Autodesk Fusion 360 part; units mm, degrees
(part 5 of 8)
  spline S109 degree 5 poles (-4.725934, 4.389539) (-4.725181, 4.387551) (-4.723672, 4.383579) (-4.721399, 4.377629) (-4.718349, 4.369712) (-4.714504, 4.359843) (-4.710627, 4.350002) (-4.706718, 4.340188) (-4.702776, 4.330401) (-4.698802, 4.320643) (-4.694795, 4.310913) (-4.690755, 4.301211) (-4.686683, 4.291538) (-4.682577, 4.281894) (-4.678439, 4.272279) (-4.674267, 4.262693) (-4.670062, 4.253137) (-4.665824, 4.243611) (-4.661551, 4.234115) (-4.657246, 4.22465) (-4.652906, 4.215215) (-4.648532, 4.205811) (-4.644124, 4.196439) (-4.639682, 4.187098) (-4.635205, 4.177788) (-4.630693, 4.168512) (-4.626147, 4.159267) (-4.621565, 4.150055) (-4.616948, 4.140877) (-4.612296, 4.131732) (-4.607608, 4.122621) (-4.602883, 4.113544) (-4.598123, 4.104502) (-4.593326, 4.095495) (-4.588492, 4.086524) (-4.583621, 4.077589) (-4.578713, 4.068689) (-4.573767, 4.059827) (-4.568784, 4.051001) (-4.563762, 4.042214) (-4.558702, 4.033464) (-4.553602, 4.024755) (-4.548462, 4.016085) (-4.543281, 4.007456) (-4.538061, 3.998867) (-4.532799, 3.99032) (-4.527498, 3.981813) (-4.522155, 3.973349) (-4.516771, 3.964927) (-4.511343, 3.95655) (-4.505871, 3.948219) (-4.500351, 3.939937) (-4.494784, 3.931705) (-4.489169, 3.923523) (-4.483506, 3.915391) (-4.477798, 3.907307) (-4.472045, 3.89927) (-4.466248, 3.891282) (-4.460403, 3.883345) (-4.454505, 3.875465) (-4.448545, 3.867651) (-4.442516, 3.859911) (-4.437505, 3.853618) (-4.433679, 3.848895) (-4.43107, 3.845708) (-4.429696, 3.844038) (-4.429564, 3.843877) knots -1 -1 -1 -1 -1 -1 -0.98571429 -0.97142857 -0.95714286 -0.94285714 -0.92857143 -0.91428571 -0.9 -0.88571429 -0.87142857 -0.85714286 -0.84285714 -0.82857143 -0.81428571 -0.8 -0.78571429 -0.77142857 -0.75714286 -0.74285714 -0.72857143 -0.71428571 -0.7 -0.68571429 -0.67142857 -0.65714286 -0.64285714 -0.62857143 -0.61428571 -0.6 -0.58571429 -0.57142857 -0.55714286 -0.54285714 -0.52857143 -0.51428571 -0.5 -0.48571429 -0.47142857 -0.45714286 -0.44285714 -0.42857143 -0.41428571 -0.4 -0.38571429 -0.37142857 -0.35714286 -0.34285714 -0.32857143 -0.31428571 -0.3 -0.28571429 -0.27142857 -0.25714286 -0.24285714 -0.22857143 -0.21428571 -0.2 -0.18571429 -0.17142857 -0.15714286 -0.14285714 -0.12857143 -0.1270499 -0.1270499 -0.1270499 -0.1270499 -0.1270499 -0.1270499
  spline S110 degree 3 poles (-4.616916, 3.6167) (-4.599749, 3.607383) (-4.580926, 3.601508) (-4.542089, 3.597304) (-4.522445, 3.599015) (-4.484919, 3.60987) (-4.467396, 3.618911) (-4.436801, 3.6432) (-4.424022, 3.658217) (-4.404939, 3.692303) (-4.398817, 3.711047) (-4.394104, 3.749826) (-4.395557, 3.76949) (-4.403528, 3.798464) (-4.407377, 3.808284) (-4.417066, 3.826956) (-4.422879, 3.835757) (-4.429564, 3.843877) knots 0 0 0 0 0.00585967 0.00585967 0.01171933 0.01171933 0.017579 0.017579 0.02343867 0.02343867 0.02929834 0.02929834 0.035158 0.035158 0.03831344 0.03831344 0.04146887 0.04146887 0.04146887 0.04146887
  spline S111 degree 5 poles (-4.616916, 3.6167) (-4.617099, 3.616799) (-4.619, 3.61783) (-4.622625, 3.619784) (-4.62799, 3.622641) (-4.635122, 3.626362) (-4.643869, 3.630807) (-4.652674, 3.63517) (-4.661533, 3.639461) (-4.670438, 3.643687) (-4.679384, 3.647858) (-4.688368, 3.651975) (-4.697391, 3.65604) (-4.706453, 3.66005) (-4.715554, 3.664005) (-4.724696, 3.667903) (-4.733877, 3.671745) (-4.743097, 3.675531) (-4.752355, 3.679265) (-4.761647, 3.682947) (-4.770974, 3.68658) (-4.780335, 3.690166) (-4.789728, 3.693703) (-4.799153, 3.697193) (-4.808611, 3.700636) (-4.818101, 3.704031) (-4.827622, 3.70738) (-4.837174, 3.710682) (-4.846757, 3.713939) (-4.85637, 3.717151) (-4.866012, 3.720318) (-4.875683, 3.723442) (-4.885383, 3.726523) (-4.89511, 3.72956) (-4.904866, 3.732555) (-4.914649, 3.735507) (-4.924459, 3.738416) (-4.934296, 3.741284) (-4.944159, 3.74411) (-4.954049, 3.746895) (-4.963964, 3.749639) (-4.973905, 3.752342) (-4.983871, 3.755005) (-4.993863, 3.757628) (-5.003879, 3.760211) (-5.013919, 3.762753) (-5.023984, 3.765257) (-5.034072, 3.767721) (-5.044184, 3.770146) (-5.05432, 3.772532) (-5.064479, 3.774879) (-5.07466, 3.777188) (-5.084865, 3.779458) (-5.095092, 3.781691) (-5.105341, 3.783885) (-5.115613, 3.786041) (-5.125906, 3.78816) (-5.136221, 3.790241) (-5.146558, 3.792285) (-5.156916, 3.794291) (-5.167294, 3.79626) (-5.177694, 3.798193) (-5.188114, 3.800088) (-5.196467, 3.801575) (-5.202741, 3.802674) (-5.206928, 3.803399) (-5.209022, 3.803759) knots 0.1270499 0.1270499 0.1270499 0.1270499 0.1270499 0.1270499 0.12857143 0.14285714 0.15714286 0.17142857 0.18571429 0.2 0.21428571 0.22857143 0.24285714 0.25714286 0.27142857 0.28571429 0.3 0.31428571 0.32857143 0.34285714 0.35714286 0.37142857 0.38571429 0.4 0.41428571 0.42857143 0.44285714 0.45714286 0.47142857 0.48571429 0.5 0.51428571 0.52857143 0.54285714 0.55714286 0.57142857 0.58571429 0.6 0.61428571 0.62857143 0.64285714 0.65714286 0.67142857 0.68571429 0.7 0.71428571 0.72857143 0.74285714 0.75714286 0.77142857 0.78571429 0.8 0.81428571 0.82857143 0.84285714 0.85714286 0.87142857 0.88571429 0.9 0.91428571 0.92857143 0.94285714 0.95714286 0.97142857 0.98571429 1 1 1 1 1 1
  arc A37 (-5.209022, 3.803759) -> (-5.340608, 3.616685) centre (0, 0) ccw
  spline S112 degree 5 poles (-5.340608, 3.616685) (-5.33956, 3.614836) (-5.337463, 3.61114) (-5.334308, 3.605607) (-5.330085, 3.598248) (-5.324779, 3.589082) (-5.319445, 3.579948) (-5.314084, 3.570845) (-5.308694, 3.561776) (-5.303277, 3.552738) (-5.297832, 3.543734) (-5.292359, 3.534762) (-5.286857, 3.525824) (-5.281328, 3.51692) (-5.27577, 3.508049) (-5.270184, 3.499213) (-5.264569, 3.490411) (-5.258926, 3.481643) (-5.253255, 3.472911) (-5.247554, 3.464213) (-5.241825, 3.455552) (-5.236067, 3.446926) (-5.23028, 3.438336) (-5.224464, 3.429783) (-5.218618, 3.421266) (-5.212744, 3.412786) (-5.206839, 3.404344) (-5.200905, 3.39594) (-5.194941, 3.387574) (-5.188947, 3.379246) (-5.182923, 3.370958) (-5.176869, 3.362708) (-5.170784, 3.354499) (-5.164668, 3.34633) (-5.158522, 3.338202) (-5.152344, 3.330115) (-5.146135, 3.322069) (-5.139894, 3.314065) (-5.133622, 3.306104) (-5.127318, 3.298185) (-5.120981, 3.290311) (-5.114611, 3.282482) (-5.108208, 3.274699) (-5.101771, 3.266961) (-5.095301, 3.25927) (-5.088796, 3.251626) (-5.082258, 3.244029) (-5.075686, 3.236479) (-5.069079, 3.228978) (-5.062437, 3.221527) (-5.055757, 3.21413) (-5.049038, 3.206787) (-5.042279, 3.199501) (-5.03548, 3.192273) (-5.028643, 3.1851) (-5.021768, 3.177982) (-5.014856, 3.170918) (-5.007907, 3.163908) (-5.000919, 3.156956) (-4.993887, 3.150069) (-4.986804, 3.143257) (-4.979664, 3.136528) (-4.973751, 3.131073) (-4.969249, 3.126989) (-4.966185, 3.124238) (-4.964572, 3.122797) (-4.964416, 3.122659) knots -1 -1 -1 -1 -1 -1 -0.98571429 -0.97142857 -0.95714286 -0.94285714 -0.92857143 -0.91428571 -0.9 -0.88571429 -0.87142857 -0.85714286 -0.84285714 -0.82857143 -0.81428571 -0.8 -0.78571429 -0.77142857 -0.75714286 -0.74285714 -0.72857143 -0.71428571 -0.7 -0.68571429 -0.67142857 -0.65714286 -0.64285714 -0.62857143 -0.61428571 -0.6 -0.58571429 -0.57142857 -0.55714286 -0.54285714 -0.52857143 -0.51428571 -0.5 -0.48571429 -0.47142857 -0.45714286 -0.44285714 -0.42857143 -0.41428571 -0.4 -0.38571429 -0.37142857 -0.35714286 -0.34285714 -0.32857143 -0.31428571 -0.3 -0.28571429 -0.27142857 -0.25714286 -0.24285714 -0.22857143 -0.21428571 -0.2 -0.18571429 -0.17142857 -0.15714286 -0.14285714 -0.12857143 -0.1270499 -0.1270499 -0.1270499 -0.1270499 -0.1270499 -0.1270499
  spline S113 degree 3 poles (-5.114894, 2.869545) (-5.096506, 2.862957) (-5.077007, 2.860025) (-5.037983, 2.861798) (-5.018831, 2.866488) (-4.983402, 2.882944) (-4.967464, 2.894554) (-4.940935, 2.923229) (-4.930598, 2.94002) (-4.916942, 2.97662) (-4.913754, 2.996079) (-4.915015, 3.035123) (-4.919453, 3.054335) (-4.931753, 3.081752) (-4.937056, 3.09087) (-4.949482, 3.107844) (-4.95657, 3.115654) (-4.964416, 3.122659) knots 0 0 0 0 0.00585967 0.00585967 0.01171933 0.01171933 0.017579 0.017579 0.02343867 0.02343867 0.02929834 0.02929834 0.035158 0.035158 0.03831344 0.03831344 0.04146887 0.04146887 0.04146887 0.04146887
  spline S114 degree 5 poles (-5.114894, 2.869545) (-5.11509, 2.869615) (-5.117126, 2.870344) (-5.121007, 2.871722) (-5.126746, 2.873726) (-5.134362, 2.876315) (-5.143685, 2.879372) (-5.153053, 2.88234) (-5.162463, 2.885228) (-5.171908, 2.888046) (-5.181386, 2.890802) (-5.190894, 2.893499) (-5.200432, 2.896139) (-5.209999, 2.898719) (-5.219598, 2.901239) (-5.229227, 2.903696) (-5.238887, 2.906091) (-5.248578, 2.908425) (-5.258296, 2.910702) (-5.268042, 2.912922) (-5.277814, 2.915089) (-5.287612, 2.917204) (-5.297435, 2.919266) (-5.307283, 2.921276) (-5.317155, 2.923235) (-5.327052, 2.925142) (-5.336973, 2.926998) (-5.346918, 2.928803) (-5.356886, 2.930559) (-5.366876, 2.932266) (-5.376889, 2.933924) (-5.386923, 2.935535) (-5.396979, 2.937099) (-5.407056, 2.938616) (-5.417155, 2.940086) (-5.427273, 2.94151) (-5.437413, 2.942889) (-5.447572, 2.944221) (-5.457751, 2.945508) (-5.46795, 2.946751) (-5.478168, 2.947949) (-5.488406, 2.949103) (-5.498661, 2.950214) (-5.508936, 2.95128) (-5.519229, 2.952304) (-5.52954, 2.953284) (-5.539868, 2.954222) (-5.550215, 2.955117) (-5.560579, 2.95597) (-5.57096, 2.956781) (-5.581358, 2.95755) (-5.591772, 2.958278) (-5.602204, 2.958964) (-5.612652, 2.959609) (-5.623116, 2.960213) (-5.633597, 2.960776) (-5.644093, 2.961298) (-5.654605, 2.96178) (-5.665132, 2.962222) (-5.675675, 2.962624) (-5.686232, 2.962986) (-5.696805, 2.963308) (-5.707393, 2.963591) (-5.715875, 2.963785) (-5.722243, 2.963913) (-5.726491, 2.963991) (-5.728616, 2.964027) knots 0.1270499 0.1270499 0.1270499 0.1270499 0.1270499 0.1270499 0.12857143 0.14285714 0.15714286 0.17142857 0.18571429 0.2 0.21428571 0.22857143 0.24285714 0.25714286 0.27142857 0.28571429 0.3 0.31428571 0.32857143 0.34285714 0.35714286 0.37142857 0.38571429 0.4 0.41428571 0.42857143 0.44285714 0.45714286 0.47142857 0.48571429 0.5 0.51428571 0.52857143 0.54285714 0.55714286 0.57142857 0.58571429 0.6 0.61428571 0.62857143 0.64285714 0.65714286 0.67142857 0.68571429 0.7 0.71428571 0.72857143 0.74285714 0.75714286 0.77142857 0.78571429 0.8 0.81428571 0.82857143 0.84285714 0.85714286 0.87142857 0.88571429 0.9 0.91428571 0.92857143 0.94285714 0.95714286 0.97142857 0.98571429 1 1 1 1 1 1
  arc A38 (-5.728616, 2.964027) -> (-5.830102, 2.759059) centre (0, 0) ccw
  spline S115 degree 5 poles (-5.830102, 2.759059) (-5.828785, 2.757391) (-5.826148, 2.754059) (-5.822186, 2.749072) (-5.816889, 2.742445) (-5.810246, 2.734196) (-5.80358, 2.725983) (-5.796892, 2.717805) (-5.790181, 2.709665) (-5.783448, 2.70156) (-5.776692, 2.693492) (-5.769913, 2.685462) (-5.763112, 2.677468) (-5.756288, 2.669512) (-5.749441, 2.661594) (-5.742572, 2.653714) (-5.735679, 2.645872) (-5.728764, 2.638069) (-5.721826, 2.630304) (-5.714865, 2.622579) (-5.707881, 2.614893) (-5.700873, 2.607247) (-5.693843, 2.599642) (-5.686789, 2.592076) (-5.679712, 2.584552) (-5.672612, 2.577068) (-5.665488, 2.569627) (-5.658341, 2.562227) (-5.651169, 2.554869) (-5.643975, 2.547554) (-5.636756, 2.540282) (-5.629513, 2.533053) (-5.622246, 2.525869) (-5.614955, 2.51873) (-5.60764, 2.511635) (-5.6003, 2.504585) (-5.592936, 2.497582) (-5.585547, 2.490624) (-5.578133, 2.483714) (-5.570694, 2.476851) (-5.563229, 2.470036) (-5.555739, 2.463271) (-5.548223, 2.456556) (-5.54068, 2.449892) (-5.533111, 2.443279) (-5.525516, 2.436717) (-5.517895, 2.430207) (-5.510248, 2.423749) (-5.502573, 2.417344) (-5.494871, 2.410995) (-5.48714, 2.404704) (-5.479379, 2.398473) (-5.471587, 2.392304) (-5.463765, 2.386198) (-5.455912, 2.380153) (-5.448031, 2.374168) (-5.440122, 2.368242) (-5.432185, 2.362375) (-5.424218, 2.356571) (-5.416216, 2.350839) (-5.408177, 2.345187) (-5.400093, 2.339627) (-5.393417, 2.335139) (-5.388344, 2.33179) (-5.384896, 2.329539) (-5.383082, 2.328361) (-5.382907, 2.328248) knots -1 -1 -1 -1 -1 -1 -0.98571429 -0.97142857 -0.95714286 -0.94285714 -0.92857143 -0.91428571 -0.9 -0.88571429 -0.87142857 -0.85714286 -0.84285714 -0.82857143 -0.81428571 -0.8 -0.78571429 -0.77142857 -0.75714286 -0.74285714 -0.72857143 -0.71428571 -0.7 -0.68571429 -0.67142857 -0.65714286 -0.64285714 -0.62857143 -0.61428571 -0.6 -0.58571429 -0.57142857 -0.55714286 -0.54285714 -0.52857143 -0.51428571 -0.5 -0.48571429 -0.47142857 -0.45714286 -0.44285714 -0.42857143 -0.41428571 -0.4 -0.38571429 -0.37142857 -0.35714286 -0.34285714 -0.32857143 -0.31428571 -0.3 -0.28571429 -0.27142857 -0.25714286 -0.24285714 -0.22857143 -0.21428571 -0.2 -0.18571429 -0.17142857 -0.15714286 -0.14285714 -0.12857143 -0.1270499 -0.1270499 -0.1270499 -0.1270499 -0.1270499 -0.1270499
  spline S116 degree 3 poles (-5.492984, 2.05513) (-5.473806, 2.051427) (-5.454088, 2.051505) (-5.415792, 2.059215) (-5.39758, 2.066773) (-5.365078, 2.088445) (-5.351099, 2.102351) (-5.329258, 2.13474) (-5.321606, 2.152912) (-5.313696, 2.191168) (-5.313516, 2.210885) (-5.320723, 2.249279) (-5.328041, 2.267588) (-5.344383, 2.292807) (-5.351015, 2.301008) (-5.365886, 2.315887) (-5.374083, 2.322523) (-5.382907, 2.328248) knots 0 0 0 0 0.00585967 0.00585967 0.01171933 0.01171933 0.017579 0.017579 0.02343867 0.02343867 0.02929834 0.02929834 0.035158 0.035158 0.03831344 0.03831344 0.04146887 0.04146887 0.04146887 0.04146887
  spline S117 degree 5 poles (-5.492984, 2.05513) (-5.493188, 2.055169) (-5.495311, 2.055579) (-5.499357, 2.056348) (-5.505335, 2.057453) (-5.513257, 2.058849) (-5.522937, 2.060447) (-5.532649, 2.061951) (-5.542389, 2.063368) (-5.552154, 2.064711) (-5.561941, 2.065988) (-5.57175, 2.067202) (-5.581578, 2.068355) (-5.591428, 2.069445) (-5.601298, 2.07047) (-5.61119, 2.071428) (-5.621103, 2.07232) (-5.631035, 2.073148) (-5.640988, 2.073914) (-5.650959, 2.074621) (-5.660947, 2.075271) (-5.670953, 2.075865) (-5.680975, 2.076404) (-5.691014, 2.076887) (-5.70107, 2.077316) (-5.711142, 2.07769) (-5.72123, 2.078009) (-5.731334, 2.078276) (-5.741453, 2.078489) (-5.751587, 2.078651) (-5.761735, 2.078762) (-5.771898, 2.078822) (-5.782075, 2.078833) (-5.792266, 2.078793) (-5.80247, 2.078705) (-5.812688, 2.078568) (-5.822918, 2.078382) (-5.833162, 2.078148) (-5.843419, 2.077866) (-5.853688, 2.077538) (-5.863969, 2.077162) (-5.874262, 2.07674) (-5.884567, 2.076272) (-5.894884, 2.075758) (-5.905213, 2.075198) (-5.915552, 2.074593) (-5.925903, 2.073943) (-5.936265, 2.073248) (-5.946638, 2.072509) (-5.957021, 2.071726) (-5.967414, 2.070899) (-5.977818, 2.070028) (-5.988232, 2.069114) (-5.998656, 2.068156) (-6.00909, 2.067156) (-6.019533, 2.066112) (-6.029986, 2.065026) (-6.040449, 2.063898) (-6.05092, 2.062728) (-6.0614, 2.061516) (-6.07189, 2.060262) (-6.082388, 2.058966) (-6.092894, 2.057629) (-6.101307, 2.056527) (-6.10762, 2.055681) (-6.11183, 2.055109) (-6.113936, 2.054821) knots 0.1270499 0.1270499 0.1270499 0.1270499 0.1270499 0.1270499 0.12857143 0.14285714 0.15714286 0.17142857 0.18571429 0.2 0.21428571 0.22857143 0.24285714 0.25714286 0.27142857 0.28571429 0.3 0.31428571 0.32857143 0.34285714 0.35714286 0.37142857 0.38571429 0.4 0.41428571 0.42857143 0.44285714 0.45714286 0.47142857 0.48571429 0.5 0.51428571 0.52857143 0.54285714 0.55714286 0.57142857 0.58571429 0.6 0.61428571 0.62857143 0.64285714 0.65714286 0.67142857 0.68571429 0.7 0.71428571 0.72857143 0.74285714 0.75714286 0.77142857 0.78571429 0.8 0.81428571 0.82857143 0.84285714 0.85714286 0.87142857 0.88571429 0.9 0.91428571 0.92857143 0.94285714 0.95714286 0.97142857 0.98571429 1 1 1 1 1 1
  arc A39 (-6.113936, 2.054821) -> (-6.182944, 1.836763) centre (0, 0) ccw
  spline S118 degree 5 poles (-6.182944, 1.836763) (-6.181388, 1.835316) (-6.178273, 1.832426) (-6.173596, 1.828102) (-6.16735, 1.82236) (-6.159525, 1.815222) (-6.151684, 1.808123) (-6.143826, 1.801063) (-6.135951, 1.794041) (-6.128059, 1.78706) (-6.120151, 1.780118) (-6.112226, 1.773216) (-6.104284, 1.766354) (-6.096326, 1.759533) (-6.088351, 1.752753) (-6.080359, 1.746014) (-6.07235, 1.739316) (-6.064325, 1.73266) (-6.056283, 1.726045) (-6.048224, 1.719473) (-6.040148, 1.712944) (-6.032056, 1.706457) (-6.023947, 1.700014) (-6.015821, 1.693614) (-6.007678, 1.687258) (-5.999519, 1.680946) (-5.991342, 1.674679) (-5.983149, 1.668457) (-5.974939, 1.66228) (-5.966712, 1.656149) (-5.958468, 1.650064) (-5.950207, 1.644026) (-5.941928, 1.638035) (-5.933633, 1.632092) (-5.92532, 1.626197) (-5.91699, 1.620351) (-5.908643, 1.614553) (-5.900278, 1.608805) (-5.891896, 1.603108) (-5.883497, 1.597461) (-5.87508, 1.591866) (-5.866645, 1.586323) (-5.858191, 1.580834) (-5.84972, 1.5754) (-5.84123, 1.570019) (-5.832723, 1.564694) (-5.824197, 1.559423) (-5.815653, 1.554208) (-5.807091, 1.54905) (-5.79851, 1.543951) (-5.789909, 1.538914) (-5.781288, 1.533941) (-5.772646, 1.529033) (-5.763983, 1.524193) (-5.7553, 1.519418) (-5.746598, 1.514706) (-5.737877, 1.510056) (-5.729137, 1.50547) (-5.720377, 1.50095) (-5.711595, 1.496506) (-5.702786, 1.492148) (-5.693949, 1.487887) (-5.686666, 1.484471) (-5.681141, 1.481935) (-5.677389, 1.480237) (-5.675417, 1.47935) (-5.675227, 1.479265) knots -1 -1 -1 -1 -1 -1 -0.98571429 -0.97142857 -0.95714286 -0.94285714 -0.92857143 -0.91428571 -0.9 -0.88571429 -0.87142857 -0.85714286 -0.84285714 -0.82857143 -0.81428571 -0.8 -0.78571429 -0.77142857 -0.75714286 -0.74285714 -0.72857143 -0.71428571 -0.7 -0.68571429 -0.67142857 -0.65714286 -0.64285714 -0.62857143 -0.61428571 -0.6 -0.58571429 -0.57142857 -0.55714286 -0.54285714 -0.52857143 -0.51428571 -0.5 -0.48571429 -0.47142857 -0.45714286 -0.44285714 -0.42857143 -0.41428571 -0.4 -0.38571429 -0.37142857 -0.35714286 -0.34285714 -0.32857143 -0.31428571 -0.3 -0.28571429 -0.27142857 -0.25714286 -0.24285714 -0.22857143 -0.21428571 -0.2 -0.18571429 -0.17142857 -0.15714286 -0.14285714 -0.12857143 -0.1270499 -0.1270499 -0.1270499 -0.1270499 -0.1270499 -0.1270499
  spline S119 degree 3 poles (-5.742322, 1.192545) (-5.722804, 1.191812) (-5.703329, 1.194899) (-5.666659, 1.208365) (-5.649814, 1.218615) (-5.621001, 1.244994) (-5.609309, 1.260871) (-5.592668, 1.296214) (-5.587879, 1.315342) (-5.585902, 1.354356) (-5.588734, 1.37387) (-5.601717, 1.410714) (-5.611744, 1.427692) (-5.631744, 1.45012) (-5.639551, 1.457212) (-5.656519, 1.469647) (-5.665633, 1.474954) (-5.675227, 1.479265) knots 0 0 0 0 0.00585967 0.00585967 0.01171933 0.01171933 0.017579 0.017579 0.02343867 0.02343867 0.02929834 0.02929834 0.035158 0.035158 0.03831344 0.03831344 0.04146887 0.04146887 0.04146887 0.04146887
  spline S120 degree 5 poles (-5.742322, 1.192545) (-5.74253, 1.192552) (-5.744691, 1.192633) (-5.748807, 1.192776) (-5.754883, 1.192955) (-5.762926, 1.193125) (-5.772736, 1.193227) (-5.782564, 1.193231) (-5.792406, 1.193145) (-5.802262, 1.192981) (-5.812129, 1.192749) (-5.822008, 1.192452) (-5.831898, 1.192091) (-5.841798, 1.191664) (-5.851709, 1.19117) (-5.861631, 1.190608) (-5.871564, 1.189976) (-5.881507, 1.189278) (-5.891459, 1.188516) (-5.901421, 1.187693) (-5.911392, 1.18681) (-5.921371, 1.18587) (-5.931358, 1.184872) (-5.941354, 1.183818) (-5.951357, 1.182706) (-5.961368, 1.181538) (-5.971386, 1.180314) (-5.981412, 1.179035) (-5.991445, 1.177702) (-6.001485, 1.176315) (-6.011532, 1.174875) (-6.021585, 1.173383) (-6.031644, 1.17184) (-6.041709, 1.170246) (-6.05178, 1.168601) (-6.061857, 1.166905) (-6.07194, 1.16516) (-6.082028, 1.163365) (-6.092121, 1.161521) (-6.10222, 1.159629) (-6.112323, 1.157688) (-6.122431, 1.1557) (-6.132544, 1.153664) (-6.142662, 1.151581) (-6.152784, 1.149451) (-6.16291, 1.147275) (-6.17304, 1.145052) (-6.183174, 1.142784) (-6.193313, 1.14047) (-6.203455, 1.138111) (-6.2136, 1.135707) (-6.223749, 1.133258) (-6.233901, 1.130765) (-6.244057, 1.128228) (-6.254216, 1.125646) (-6.264378, 1.123021) (-6.274542, 1.120352) (-6.28471, 1.11764) (-6.29488, 1.114885) (-6.305052, 1.112087) (-6.315227, 1.109247) (-6.325404, 1.106364) (-6.335584, 1.103439) (-6.343729, 1.101065) (-6.349839, 1.099266) (-6.353913, 1.098058) (-6.35595, 1.097451) knots 0.1270499 0.1270499 0.1270499 0.1270499 0.1270499 0.1270499 0.12857143 0.14285714 0.15714286 0.17142857 0.18571429 0.2 0.21428571 0.22857143 0.24285714 0.25714286 0.27142857 0.28571429 0.3 0.31428571 0.32857143 0.34285714 0.35714286 0.37142857 0.38571429 0.4 0.41428571 0.42857143 0.44285714 0.45714286 0.47142857 0.48571429 0.5 0.51428571 0.52857143 0.54285714 0.55714286 0.57142857 0.58571429 0.6 0.61428571 0.62857143 0.64285714 0.65714286 0.67142857 0.68571429 0.7 0.71428571 0.72857143 0.74285714 0.75714286 0.77142857 0.78571429 0.8 0.81428571 0.82857143 0.84285714 0.85714286 0.87142857 0.88571429 0.9 0.91428571 0.92857143 0.94285714 0.95714286 0.97142857 0.98571429 1 1 1 1 1 1
  arc A40 (-6.35595, 1.097451) -> (-6.390863, 0.871415) centre (0, 0) ccw
  spline S121 degree 5 poles (-6.390863, 0.871415) (-6.389104, 0.870222) (-6.385585, 0.867841) (-6.380302, 0.864282) (-6.373253, 0.859562) (-6.36443, 0.853701) (-6.355597, 0.847882) (-6.346754, 0.842104) (-6.337899, 0.836368) (-6.329035, 0.830672) (-6.320159, 0.825019) (-6.311274, 0.819408) (-6.302377, 0.813839) (-6.293471, 0.808312) (-6.284554, 0.802829) (-6.275627, 0.797389) (-6.26669, 0.791992) (-6.257743, 0.786639) (-6.248785, 0.78133) (-6.239818, 0.776065) (-6.23084, 0.770845) (-6.221852, 0.765669) (-6.212855, 0.760539) (-6.203847, 0.755455) (-6.19483, 0.750416) (-6.185802, 0.745424) (-6.176765, 0.740478) (-6.167718, 0.73558) (-6.158661, 0.730728) (-6.149595, 0.725925) (-6.140518, 0.72117) (-6.131432, 0.716464) (-6.122336, 0.711807) (-6.113231, 0.7072) (-6.104116, 0.702643) (-6.094991, 0.698137) (-6.085857, 0.693681) (-6.076713, 0.689278) (-6.067559, 0.684926) (-6.058396, 0.680627) (-6.049223, 0.676383) (-6.040041, 0.672193) (-6.030849, 0.668059) (-6.021647, 0.663981) (-6.012436, 0.65996) (-6.003215, 0.655995) (-5.993985, 0.652088) (-5.984745, 0.648238) (-5.975496, 0.644447) (-5.966237, 0.640718) (-5.956968, 0.637053) (-5.947689, 0.633454) (-5.938399, 0.629924) (-5.929099, 0.626462) (-5.919789, 0.623068) (-5.910469, 0.61974) (-5.90114, 0.616476) (-5.891802, 0.613278) (-5.882455, 0.610148) (-5.873098, 0.607097) (-5.863727, 0.604135) (-5.854343, 0.601272) (-5.846624, 0.599008) (-5.840777, 0.597346) (-5.83681, 0.59624) (-5.834725, 0.595664) (-5.834525, 0.595609) knots -1 -1 -1 -1 -1 -1 -0.98571429 -0.97142857 -0.95714286 -0.94285714 -0.92857143 -0.91428571 -0.9 -0.88571429 -0.87142857 -0.85714286 -0.84285714 -0.82857143 -0.81428571 -0.8 -0.78571429 -0.77142857 -0.75714286 -0.74285714 -0.72857143 -0.71428571 -0.7 -0.68571429 -0.67142857 -0.65714286 -0.64285714 -0.62857143 -0.61428571 -0.6 -0.58571429 -0.57142857 -0.55714286 -0.54285714 -0.52857143 -0.51428571 -0.5 -0.48571429 -0.47142857 -0.45714286 -0.44285714 -0.42857143 -0.41428571 -0.4 -0.38571429 -0.37142857 -0.35714286 -0.34285714 -0.32857143 -0.31428571 -0.3 -0.28571429 -0.27142857 -0.25714286 -0.24285714 -0.22857143 -0.21428571 -0.2 -0.18571429 -0.17142857 -0.15714286 -0.14285714 -0.12857143 -0.1270499 -0.1270499 -0.1270499 -0.1270499 -0.1270499 -0.1270499
  spline S122 degree 3 poles (-5.857066, 0.302007) (-5.837664, 0.304263) (-5.818889, 0.310287) (-5.784704, 0.329192) (-5.769621, 0.341893) (-5.745173, 0.372361) (-5.736041, 0.389837) (-5.724991, 0.427306) (-5.723178, 0.446941) (-5.727179, 0.4858) (-5.732956, 0.504653) (-5.751411, 0.539083) (-5.763913, 0.554331) (-5.787102, 0.573444) (-5.7959, 0.579261) (-5.814567, 0.58896) (-5.824385, 0.592814) (-5.834525, 0.595609) knots 0 0 0 0 0.00585967 0.00585967 0.01171933 0.01171933 0.017579 0.017579 0.02343867 0.02343867 0.02929834 0.02929834 0.035158 0.035158 0.03831344 0.03831344 0.04146887 0.04146887 0.04146887 0.04146887
  circle A41 centre (0, 0) radius 0.5
  circle A42 centre (0, 0) radius 2.5
  constraint coincident A0.centre A1.centre
extrude "押し出し3" cut sketch "スケッチ1 (2)" against normal blind 9.4 contours A42 picked at (-1.785141, 0.394672) in component "Spur Gear (41 teeth)"
component "Spur Gear (41 teeth)" placed x (1, 0, 0) y (0, 1, 0) z (0, 0, 1) at (0, 0, 0)

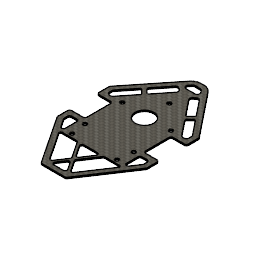
design "底板v2"
Autodesk Fusion 360 part; units mm, degrees
sketch "スケッチ1" plane through (0, 0, 0) normal (0, 0, 1) x (1, 0, 0)
  line L0 (0, 0) -> (-44.2, 0)
  line L1 (-44.2, 0) -> (-44.2, 42)
  line L2 (-44.2, 42) -> (0, 42)
  line L3 (0, 42) -> (0, 0)
  dimension "d1" = 44.2
  dimension "d2" = 42
  constraint horizontal L0
  constraint vertical L1
  constraint horizontal L2
  constraint vertical L3
  constraint coincident L0.start L3.end
  measures "d1" distance of L0.start L0.end
  measures "d2" distance of L0.start L2.end
extrude "押し出し1" add sketch "スケッチ1" along normal blind 1
sketch "スケッチ2" plane through (0, 0, 1) normal (0, 0, 1) x (-1, 0, 0)
  line L0 (0, -42) -> (44.2, -42)
  line L1 (44.2, -42) -> (44.2, 0)
  line L2 (44.2, 0) -> (0, 0)
  line L3 (0, 0) -> (0, -42)
  line L4 (0, 0) -> (22.1, 0)
  line L5 (22.1, 0) -> (-12.9, 0)
  line L6 (-12.9, 0) -> (-12.9, -42)
  line L7 (-12.9, -42) -> (22.1, -42)
  line L8 (22.1, -42) -> (22.1, 0)
  line L9 (-12.9, 0) -> (-12.9, -22.4)
  line L10 (-12.9, -22.4) -> (-12.9, -11.4)
  line L11 (-12.9, -11.4) -> (0, -11.4)
  line L12 (0, -11.4) -> (0, -33.4)
  line L13 (0, -33.4) -> (-12.9, -33.4)
  line L14 (-12.9, -33.4) -> (-12.9, -11.4)
  line L15 (22.1, 0) -> (57.1, 0)
  line L16 (57.1, 0) -> (57.1, -22.4)
  line L17 (57.1, -11.4) -> (44.2, -11.4)
  line L18 (44.2, -33.4) -> (57.1, -33.4)
  line L19 (57.1, -42) -> (22.1, -42)
  line L20 (57.1, 0) -> (57.1, -42)
  dimension "d5" = 35
  dimension "d6" = 42
  dimension "d7" = 22.4
  dimension "d8" = 11
  dimension "d9" = 22
  constraint coincident L2.end L3.start
  constraint midpoint L2 L4.end
  constraint horizontal L5
  constraint vertical L6
  constraint horizontal L7
  constraint vertical L8
  constraint perpendicular L5 L9
  constraint parallel L6 L10
  constraint horizontal L11
  constraint vertical L12
  constraint horizontal L13
  constraint vertical L14
  constraint symmetric L4.end L8 L5.start
  constraint symmetric L5.end L8 L15.end
  constraint symmetric L6.end L8 L19.start
  constraint symmetric L7.end L8 L19.end
  constraint symmetric L8 L9.end L16.end
  constraint symmetric L8 L10.end L17.start
  constraint symmetric L8 L11.end L17.end
  constraint symmetric L8 L12.end L18.start
  constraint symmetric L8 L13.end L18.end
  measures "d5" distance of L4.end L5.end
  measures "d6" distance of L4.end L7.end
  measures "d7" distance of L5.end L9.end
  measures "d8" distance of L9.end L10.end
  measures "d9" distance of L10.end L13.end
extrude "押し出し2" add sketch "スケッチ2" against normal blind 1 contours L3 L6 L7 L13 | L1 L18 L19 L20 | L3 L5 L6 L9 L11 | L1 L15 L16 L17 L20
sketch "スケッチ3" plane through (0, 0, 0) normal (0, 0, -1) x (1, 0, 0)
  line L0 (-57.1, -42) -> (12.9, -42)
  line L1 (12.9, -42) -> (12.9, -33.4)
  line L2 (12.9, -33.4) -> (0, -33.4)
  line L3 (0, -33.4) -> (0, -11.4)
  line L4 (0, -11.4) -> (12.9, -11.4)
  line L5 (12.9, -11.4) -> (12.9, 0)
  line L6 (12.9, 0) -> (-57.1, 0)
  line L7 (-57.1, 0) -> (-57.1, -11.4)
  line L8 (-57.1, -11.4) -> (-44.2, -11.4)
  line L9 (-44.2, -11.4) -> (-44.2, -33.4)
  line L10 (-44.2, -33.4) -> (-57.1, -33.4)
  line L11 (-57.1, -33.4) -> (-57.1, -42)
  line L12 (-44.2, -22.4) -> (0, -22.4)
  line L13 (-44.2, -22.4) -> (-22.1, -22.4)
  line L14 (-22.1, -22.4) -> (-22.1, 37.6)
  line L15 (-22.1, 37.6) -> (-12.1, 37.6)
  line L16 (-12.1, 37.6) -> (12.9, 0)
  line L17 (-32.1, 37.6) -> (-57.1, 0)
  line L18 (-22.1, 37.6) -> (-32.1, 37.6)
  dimension "d12" = 60
  dimension "d13" = 10
  constraint midpoint L9 L12.start
  constraint midpoint L3 L12.end
  constraint midpoint L12 L13.end
  constraint perpendicular L12 L14
  constraint perpendicular L14 L15
  constraint coincident L5.end L6.start
  constraint symmetric L15.start L14 L18.start
  constraint symmetric L14 L15.end L17.start
  constraint symmetric L14 L5.end L6.end
  measures "d12" distance of L13.end L14.end
  measures "d13" distance of L14.end L15.end
extrude "押し出し3" add sketch "スケッチ3" against normal blind 1 contours L6 L14 L15 L16 | L6 L14 L17 L18
sketch "スケッチ4" plane through (0, 0, 1) normal (0, 0, 1) x (-1, 0, 0)
  line L0 (-12.9, -42) -> (57.1, -42)
  line L1 (57.1, -42) -> (57.1, -33.4)
  line L2 (57.1, -33.4) -> (44.2, -33.4)
  line L3 (44.2, -33.4) -> (44.2, -11.4)
  line L4 (44.2, -11.4) -> (57.1, -11.4)
  line L5 (57.1, -11.4) -> (57.1, 0)
  line L6 (57.1, 0) -> (32.1, 37.6)
  line L7 (32.1, 37.6) -> (12.1, 37.6)
  line L8 (12.1, 37.6) -> (-12.9, 0)
  line L9 (-12.9, 0) -> (-12.9, -11.4)
  line L10 (-12.9, -11.4) -> (0, -11.4)
  line L11 (0, -11.4) -> (0, -33.4)
  line L12 (0, -33.4) -> (-12.9, -33.4)
  line L13 (-12.9, -33.4) -> (-12.9, -42)
  line L14 (-12.9, -42) -> (22.1, -42)
  line L15 (0, -11.4) -> (44.2, -33.4)
  line L16 (0, -33.4) -> (44.2, -11.4)
  line L17 (22.1, -22.4) -> (22.1, -42)
  line L18 (57.1, -33.4) -> (57.1, -44.8)
  line L19 (57.1, -44.8) -> (-12.9, -44.8)
  line L20 (-12.9, -44.8) -> (-12.9, -33.4)
  line L21 (-12.9, -33.4) -> (57.1, -33.4)
  line L22 (57.1, -33.4) -> (57.1, -44.8)
  line L23 (22.1, -22.4) -> (22.1, -82.4)
  line L24 (22.1, -82.4) -> (27.1, -82.4)
  line L25 (22.1, -82.4) -> (17.1, -82.4)
  line L26 (57.1, -44.8) -> (27.1, -82.4)
  line L27 (17.1, -82.4) -> (-12.9, -44.8)
  dimension "d16" = 11.4
  dimension "d17" = 60
  dimension "d18" = 5
  dimension "d19" = 5
  constraint coincident L0.start L13.end
  constraint midpoint L0 L14.end
  constraint coincident L10.end L11.start
  constraint coincident L2.end L3.start
  constraint coincident L11.end L12.start
  constraint coincident L3.end L4.start
  constraint midpoint L16 L17.start
  constraint coincident L1.end L2.start
  constraint perpendicular L2 L18
  constraint horizontal L19
  constraint vertical L20
  constraint horizontal L21
  constraint vertical L22
  constraint coincident L12.end L13.start
  constraint parallel L17 L23
  constraint perpendicular L23 L24
  constraint perpendicular L23 L25
  measures "d16" distance of L1.end L18.end
  measures "d17" distance of L17.start L23.end
  measures "d18" distance of L23.end L24.end
  measures "d19" distance of L23.end L25.end
extrude "押し出し4" add sketch "スケッチ4" against normal blind 1 contours L0 L14 L19 L20 L23 | L0 L18 L19 L22 L23 | L19 L23 L25 L27 | L19 L23 L24 L26
fillet "フィレット1" radius 8 2 edges at (-27.1, 82.4, 0.5) (-17.1, 82.4, 0.5)
sketch "スケッチ5" plane through (0, 0, 1) normal (0, 0, 1) x (-1, 0, 0)
  arc A0 (14.698, -79.3894) -> (20.9514, -82.4) centre (20.9514, -74.4) ccw
  line L0 (29.502, -79.3894) -> (57.1, -44.8)
  line L1 (57.1, -44.8) -> (57.1, -33.4)
  line L2 (57.1, -33.4) -> (44.2, -33.4)
  line L3 (44.2, -33.4) -> (44.2, -11.4)
  line L4 (44.2, -11.4) -> (57.1, -11.4)
  line L5 (57.1, -11.4) -> (57.1, 0)
  line L6 (57.1, 0) -> (32.1, 37.6)
  line L7 (32.1, 37.6) -> (12.1, 37.6)
  line L8 (12.1, 37.6) -> (-12.9, 0)
  line L9 (-12.9, 0) -> (-12.9, -11.4)
  line L10 (-12.9, -11.4) -> (0, -11.4)
  line L11 (0, -11.4) -> (0, -33.4)
  line L12 (0, -33.4) -> (-12.9, -33.4)
  line L13 (-12.9, -33.4) -> (-12.9, -44.8)
  line L14 (-12.9, -44.8) -> (14.698, -79.3894)
  line L15 (0, -33.4) -> (44.2, -11.4)
  line L16 (44.2, -33.4) -> (0, -11.4)
  line L17 (22.1, -22.4) -> (22.1, -35.684)
  circle A1 centre (22.1, -35.684) radius 7.5
  line L18 (20.9514, -82.4) -> (23.2486, -82.4)
  arc A2 (23.2486, -82.4) -> (29.502, -79.3894) centre (23.2486, -74.4) ccw
  dimension "d24" = 13.284
  dimension "d25" = 15
  constraint coincident L11.end L12.start
  constraint coincident L3.end L4.start
  constraint coincident L2.end L3.start
  constraint coincident L10.end L11.start
  constraint midpoint L15 L17.start
  constraint parallel L11 L17
  constraint coincident L17.end A1.centre
  measures "d24" distance of L17.start L17.end
  measures "d25" diameter of A1
extrude "押し出し5" cut sketch "スケッチ5" against normal blind 16 contours A1
sketch "スケッチ8" plane through (0, 0, 1) normal (0, 0, 1) x (-1, 0, 0)
  line L0 (57.1, -44.8) -> (57.1, -33.4)
  line L1 (57.1, -33.4) -> (44.2, -33.4)
  line L2 (44.2, -33.4) -> (44.2, -11.4)
  line L3 (44.2, -11.4) -> (57.1, -11.4)
  line L4 (57.1, -11.4) -> (57.1, 0)
  line L5 (57.1, 0) -> (32.1, 37.6)
  line L6 (32.1, 37.6) -> (12.1, 37.6)
  line L7 (12.1, 37.6) -> (-12.9, 0)
  line L8 (-12.9, 0) -> (-12.9, -11.4)
  line L9 (-12.9, -11.4) -> (0, -11.4)
  line L10 (0, -11.4) -> (0, -33.4)
  line L11 (0, -33.4) -> (-12.9, -33.4)
  line L12 (-12.9, -33.4) -> (-12.9, -44.8)
  line L13 (-12.9, -44.8) -> (14.698, -79.3894)
  arc A0 (14.698, -79.3894) -> (20.9514, -82.4) centre (20.9514, -74.4) ccw
  line L14 (20.9514, -82.4) -> (23.2486, -82.4)
  arc A1 (23.2486, -82.4) -> (29.502, -79.3894) centre (23.2486, -74.4) ccw
  line L15 (29.502, -79.3894) -> (57.1, -44.8)
  circle A2 centre (22.1, -35.684) radius 7.5
  line L16 (0, -22.4) -> (0, -7.4)
  line L17 (0, -7.4) -> (2.5, -7.4)
  line L18 (0, -22.4) -> (44.2, -22.4)
  circle A3 centre (2.5, -7.4) radius 1.5
  circle A4 centre (2.5, -37.4) radius 1.5
  line L19 (22.1, -22.4) -> (22.1, -16)
  circle A5 centre (41.7, -7.4) radius 1.5
  circle A6 centre (41.7, -37.4) radius 1.5
  dimension "d37" = 15
  dimension "d38" = 2.5
  dimension "d39" = 3
  constraint midpoint L10 L16.start
  constraint parallel L10 L16
  constraint perpendicular L16 L17
  constraint midpoint L2 L18.end
  constraint coincident L17.end A3.centre
  constraint symmetric L18 A3 A4
  constraint midpoint L18 L19.start
  constraint perpendicular L18 L19
  constraint symmetric A3 L19 A5
  constraint symmetric A4 L19 A6
  measures "d37" distance of L16.start L16.end
  measures "d38" distance of L16.end L17.end
  measures "d39" diameter of A3
extrude "押し出し7" cut sketch "スケッチ8" against normal blind 14 contours A3 | A4 | A5 | A6
sketch "スケッチ9" plane through (0, 0, 1) normal (0, 0, 1) x (-1, 0, 0)
  circle A0 centre (2.5, -37.4) radius 1.5
  circle A1 centre (41.7, -37.4) radius 1.5
  circle A2 centre (2.5, -7.4) radius 1.5
  circle A3 centre (41.7, -7.4) radius 1.5
  line L0 (57.1, -44.8) -> (57.1, -33.4)
  line L1 (57.1, -33.4) -> (44.2, -33.4)
  line L2 (44.2, -33.4) -> (44.2, -11.4)
  line L3 (44.2, -11.4) -> (57.1, -11.4)
  line L4 (57.1, -11.4) -> (57.1, 0)
  line L5 (57.1, 0) -> (32.1, 37.6)
  line L6 (32.1, 37.6) -> (12.1, 37.6)
  line L7 (12.1, 37.6) -> (-12.9, 0)
  line L8 (-12.9, 0) -> (-12.9, -11.4)
  line L9 (-12.9, -11.4) -> (0, -11.4)
  line L10 (0, -11.4) -> (0, -33.4)
  line L11 (0, -33.4) -> (-12.9, -33.4)
  line L12 (-12.9, -33.4) -> (-12.9, -44.8)
  line L13 (-12.9, -44.8) -> (14.698, -79.3894)
  arc A4 (14.698, -79.3894) -> (20.9514, -82.4) centre (20.9514, -74.4) ccw
  line L14 (20.9514, -82.4) -> (23.2486, -82.4)
  arc A5 (23.2486, -82.4) -> (29.502, -79.3894) centre (23.2486, -74.4) ccw
  line L15 (29.502, -79.3894) -> (57.1, -44.8)
  circle A6 centre (22.1, -35.684) radius 7.5
  circle A7 centre (22.1, -35.684) radius 16
  line L16 (22.1, -35.684) -> (22.1, -55.684)
  circle A8 centre (22.1, -55.684) radius 1.5
  circle A9 centre (22.1, -55.684) radius 2.5
  dimension "d42" = 32
  dimension "d43" = 20
  dimension "d44" = 3
  dimension "d45" = 5
  constraint concentric A6 A7
  constraint coincident A6.centre A7.centre
  constraint vertical L16
  constraint coincident L16.end A8.centre
  measures "d42" diameter of A7
  measures "d43" distance of A6.centre L16.end
  measures "d44" diameter of A8
  measures "d45" diameter of A9
extrude "押し出し8" cut sketch "スケッチ9" against normal blind 4 contours A8
sketch "スケッチ11" plane through (0, 0, 1) normal (0, 0, 1) x (-1, 0, 0)
  circle A0 centre (22.1, -55.684) radius 1.5
  circle A1 centre (2.5, -37.4) radius 1.5
  circle A2 centre (41.7, -37.4) radius 1.5
  circle A3 centre (2.5, -7.4) radius 1.5
  circle A4 centre (41.7, -7.4) radius 1.5
  line L0 (57.1, -44.8) -> (57.1, -33.4)
  line L1 (57.1, -33.4) -> (44.2, -33.4)
  line L2 (44.2, -33.4) -> (44.2, -11.4)
  line L3 (44.2, -11.4) -> (57.1, -11.4)
  line L4 (57.1, -11.4) -> (57.1, 0)
  line L5 (57.1, 0) -> (32.1, 37.6)
  line L6 (32.1, 37.6) -> (12.1, 37.6)
  line L7 (12.1, 37.6) -> (-12.9, 0)
  line L8 (-12.9, 0) -> (-12.9, -11.4)
  line L9 (-12.9, -11.4) -> (0, -11.4)
  line L10 (0, -11.4) -> (0, -33.4)
  line L11 (0, -33.4) -> (-12.9, -33.4)
  line L12 (-12.9, -33.4) -> (-12.9, -44.8)
  line L13 (-12.9, -44.8) -> (14.698, -79.3894)
  arc A5 (14.698, -79.3894) -> (20.9514, -82.4) centre (20.9514, -74.4) ccw
  line L14 (20.9514, -82.4) -> (23.2486, -82.4)
  arc A6 (23.2486, -82.4) -> (29.502, -79.3894) centre (23.2486, -74.4) ccw
  line L15 (29.502, -79.3894) -> (57.1, -44.8)
  circle A7 centre (22.1, -35.684) radius 7.5
  line L16 (0, -11.4) -> (4, -11.4)
  line L17 (4, -11.4) -> (4, 4.5)
  circle A8 centre (4, 4.5) radius 1.5
  line L18 (44.2, -11.4) -> (0, -11.4)
  line L19 (22.1, -11.4) -> (22.1, -8)
  circle A9 centre (40.2, 4.5) radius 1.5
  dimension "d48" = 4
  dimension "d49" = 15.9
  dimension "d50" = 3
  constraint coincident L9.end L10.start
  constraint perpendicular L10 L16
  constraint perpendicular L16 L17
  constraint coincident L17.end A8.centre
  constraint coincident L2.end L3.start
  constraint midpoint L18 L19.start
  constraint perpendicular L18 L19
  constraint symmetric A8 L19 A9
  measures "d48" distance of L9.end L16.end
  measures "d49" distance of L16.end L17.end
  measures "d50" diameter of A8
extrude "押し出し9" cut sketch "スケッチ11" against normal blind 1 contours A8 | A9
sketch "スケッチ13" plane through (0, 0, 1) normal (0, 0, 1) x (-1, 0, 0)
  circle A0 centre (4, 4.5) radius 1.5
  circle A1 centre (40.2, 4.5) radius 1.5
  circle A2 centre (22.1, -55.684) radius 1.5
  circle A3 centre (2.5, -37.4) radius 1.5
  circle A4 centre (41.7, -37.4) radius 1.5
  circle A5 centre (2.5, -7.4) radius 1.5
  circle A6 centre (41.7, -7.4) radius 1.5
  line L0 (57.1, -44.8) -> (57.1, -33.4)
  line L1 (57.1, -33.4) -> (44.2, -33.4)
  line L2 (44.2, -33.4) -> (44.2, -11.4)
  line L3 (44.2, -11.4) -> (57.1, -11.4)
  line L4 (57.1, -11.4) -> (57.1, 0)
  line L5 (57.1, 0) -> (32.1, 37.6)
  line L6 (32.1, 37.6) -> (12.1, 37.6)
  line L7 (12.1, 37.6) -> (-12.9, 0)
  line L8 (-12.9, 0) -> (-12.9, -11.4)
  line L9 (-12.9, -11.4) -> (0, -11.4)
  line L10 (0, -11.4) -> (0, -33.4)
  line L11 (0, -33.4) -> (-12.9, -33.4)
  line L12 (-12.9, -33.4) -> (-12.9, -44.8)
  line L13 (-12.9, -44.8) -> (14.698, -79.3894)
  arc A7 (14.698, -79.3894) -> (20.9514, -82.4) centre (20.9514, -74.4) ccw
  line L14 (20.9514, -82.4) -> (23.2486, -82.4)
  arc A8 (23.2486, -82.4) -> (29.502, -79.3894) centre (23.2486, -74.4) ccw
  line L15 (29.502, -79.3894) -> (57.1, -44.8)
  circle A9 centre (22.1, -35.684) radius 7.5
  line L16 (44.2, -33.4) -> (45.7, -33.4)
  line L17 (45.7, -33.4) -> (45.7, -11.4)
  line L18 (22.1, -35.684) -> (22.1, -31)
  line L19 (-1.5, -33.4) -> (-1.5, -11.4)
  dimension "d53" = 1.5
  constraint coincident L1.end L2.start
  constraint perpendicular L2 L16
  constraint coincident L3 L17.end
  constraint perpendicular L3 L17
  constraint coincident A9.centre L18.start
  constraint parallel L2 L18
  constraint symmetric L16.end L18 L19.start
  constraint symmetric L17.end L18 L19.end
  measures "d53" distance of L1.end L16.end
extrude "押し出し10" add sketch "スケッチ13" against normal blind 1 contours L1 L2 L3 L16 L17 | L9 L10 L11 L19
fillet "フィレット4" radius 1.5 4 edges at (1.5, 33.4, 0.5) (1.5, 11.4, 0.5) (-45.7, 11.4, 0.5) (-45.7, 33.4, 0.5)
sketch "スケッチ14" plane through (0, 0, 1) normal (0, 0, 1) x (-1, 0, 0)
  circle A0 centre (4, 4.5) radius 1.5
  circle A1 centre (40.2, 4.5) radius 1.5
  circle A2 centre (22.1, -55.684) radius 1.5
  circle A3 centre (2.5, -37.4) radius 1.5
  circle A4 centre (41.7, -37.4) radius 1.5
  circle A5 centre (2.5, -7.4) radius 1.5
  circle A6 centre (41.7, -7.4) radius 1.5
  line L0 (57.1, -44.8) -> (57.1, -33.4)
  line L1 (57.1, -33.4) -> (47.2, -33.4)
  arc A7 (45.7, -31.9) -> (47.2, -33.4) centre (47.2, -31.9) ccw
  line L2 (45.7, -31.9) -> (45.7, -12.9)
  arc A8 (47.2, -11.4) -> (45.7, -12.9) centre (47.2, -12.9) ccw
  line L3 (47.2, -11.4) -> (57.1, -11.4)
  line L4 (57.1, -11.4) -> (57.1, 0)
  line L5 (57.1, 0) -> (32.1, 37.6)
  line L6 (32.1, 37.6) -> (12.1, 37.6)
  line L7 (12.1, 37.6) -> (-12.9, 0)
  line L8 (-12.9, 0) -> (-12.9, -11.4)
  line L9 (-12.9, -11.4) -> (-3, -11.4)
  arc A9 (-1.5, -12.9) -> (-3, -11.4) centre (-3, -12.9) ccw
  line L10 (-1.5, -12.9) -> (-1.5, -31.9)
  arc A10 (-3, -33.4) -> (-1.5, -31.9) centre (-3, -31.9) ccw
  line L11 (-3, -33.4) -> (-12.9, -33.4)
  line L12 (-12.9, -33.4) -> (-12.9, -44.8)
  line L13 (-12.9, -44.8) -> (14.698, -79.3894)
  arc A11 (14.698, -79.3894) -> (20.9514, -82.4) centre (20.9514, -74.4) ccw
  line L14 (20.9514, -82.4) -> (23.2486, -82.4)
  arc A12 (23.2486, -82.4) -> (29.502, -79.3894) centre (23.2486, -74.4) ccw
  line L15 (29.502, -79.3894) -> (57.1, -44.8)
  circle A13 centre (22.1, -35.684) radius 7.5
  line L16 (22.1, 37.6) -> (22.1, 33.6)
  line L17 (22.1, 33.6) -> (-7.4746, 33.6)
  line L18 (-7.4746, 33.6) -> (72, 33.6)
  line L19 (39.3346, 26.7192) -> (36.0037, 24.5045)
  line L20 (36.0037, 24.5045) -> (18.8706, 50.2727)
  line L21 (18.8706, 50.2727) -> (66.4611, -21.3035)
  line L22 (5.2635, 27.318) -> (8.5945, 25.1032)
  line L23 (8.5945, 25.1032) -> (24.6977, 49.3225)
  line L24 (24.6977, 49.3225) -> (-17.0536, -13.4715)
  line L25 (22.1, 33.6) -> (22.1, 7.6)
  line L26 (22.1, 7.6) -> (55, 7.6)
  line L27 (55, 7.6) -> (-14, 7.6)
  dimension "d58" = 4
  dimension "d59" = 4
  dimension "d60" = 4
  dimension "d61" = 26
  constraint midpoint L6 L16.start
  constraint perpendicular L6 L16
  constraint perpendicular L16 L17
  constraint perpendicular L16 L18
  constraint coincident L5 L19.start
  constraint perpendicular L5 L19
  constraint perpendicular L19 L20
  constraint perpendicular L19 L21
  constraint coincident L7 L22.start
  constraint perpendicular L7 L22
  constraint perpendicular L22 L23
  constraint parallel L23 L24
  constraint perpendicular L17 L25
  constraint perpendicular L25 L26
  constraint parallel L26 L27
  measures "d58" distance of L16.start L16.end
  measures "d59" distance of L19.start L19.end
  measures "d60" distance of L22.start L22.end
  measures "d61" distance of L16.end L25.end
extrude "押し出し11" cut sketch "スケッチ14" against normal blind 11 contours L18 L20 L21 L25 L26 L27 | L17 L18 L23 L24 L25 L27
fillet "フィレット5" radius 1 4 edges at (3.0433, -7.6, 0.5) (-47.2433, -7.6, 0.5) (-29.9561, -33.6, 0.5) (-14.2439, -33.6, 0.5)
sketch "スケッチ15" plane through (0, 0, 1) normal (0, 0, 1) x (-1, 0, 0)
  line L0 (45.3776, 7.6) -> (-1.1776, 7.6)
  arc A0 (-2.0103, 9.1537) -> (-1.1776, 7.6) centre (-1.1776, 8.6) ccw
  line L1 (-2.0103, 9.1537) -> (13.9471, 33.1537)
  arc A1 (14.7799, 33.6) -> (13.9471, 33.1537) centre (14.7799, 32.6) ccw
  line L2 (14.7799, 33.6) -> (29.4201, 33.6)
  arc A2 (30.2529, 33.1537) -> (29.4201, 33.6) centre (29.4201, 32.6) ccw
  line L3 (30.2529, 33.1537) -> (46.2103, 9.1537)
  arc A3 (45.3776, 7.6) -> (46.2103, 9.1537) centre (45.3776, 8.6) ccw
  circle A4 centre (4, 4.5) radius 1.5
  circle A5 centre (40.2, 4.5) radius 1.5
  circle A6 centre (22.1, -55.684) radius 1.5
  circle A7 centre (2.5, -37.4) radius 1.5
  circle A8 centre (41.7, -37.4) radius 1.5
  circle A9 centre (2.5, -7.4) radius 1.5
  circle A10 centre (41.7, -7.4) radius 1.5
  line L4 (57.1, -44.8) -> (57.1, -33.4)
  line L5 (57.1, -33.4) -> (47.2, -33.4)
  arc A11 (45.7, -31.9) -> (47.2, -33.4) centre (47.2, -31.9) ccw
  line L6 (45.7, -31.9) -> (45.7, -12.9)
  arc A12 (47.2, -11.4) -> (45.7, -12.9) centre (47.2, -12.9) ccw
  line L7 (47.2, -11.4) -> (57.1, -11.4)
  line L8 (57.1, -11.4) -> (57.1, 0)
  line L9 (57.1, 0) -> (32.1, 37.6)
  line L10 (32.1, 37.6) -> (12.1, 37.6)
  line L11 (12.1, 37.6) -> (-12.9, 0)
  line L12 (-12.9, 0) -> (-12.9, -11.4)
  line L13 (-12.9, -11.4) -> (-3, -11.4)
  arc A13 (-1.5, -12.9) -> (-3, -11.4) centre (-3, -12.9) ccw
  line L14 (-1.5, -12.9) -> (-1.5, -31.9)
  arc A14 (-3, -33.4) -> (-1.5, -31.9) centre (-3, -31.9) ccw
  line L15 (-3, -33.4) -> (-12.9, -33.4)
  line L16 (-12.9, -33.4) -> (-12.9, -44.8)
  line L17 (-12.9, -44.8) -> (14.698, -79.3894)
  arc A15 (14.698, -79.3894) -> (20.9514, -82.4) centre (20.9514, -74.4) ccw
  line L18 (20.9514, -82.4) -> (23.2486, -82.4)
  arc A16 (23.2486, -82.4) -> (29.502, -79.3894) centre (23.2486, -74.4) ccw
  line L19 (29.502, -79.3894) -> (57.1, -44.8)
  circle A17 centre (22.1, -35.684) radius 7.5
  line L20 (22.1, -82.4) -> (22.1, -78.4)
  line L21 (39.4209, -66.9578) -> (36.2942, -64.463)
  line L22 (3.5407, -65.4057) -> (6.6674, -62.911)
  line L23 (36.2942, -64.463) -> (68.5013, -24.0969)
  line L24 (68.5013, -24.0969) -> (13.1707, -93.4445)
  line L25 (6.6674, -62.911) -> (32.8287, -95.6997)
  line L26 (32.8287, -95.6997) -> (-18.8846, -30.8857)
  line L27 (22.1, -78.4) -> (16.5, -78.4)
  line L28 (16.5, -78.4) -> (32, -78.4)
  line L29 (-7.95, -33.4) -> (-7.95, -37.4)
  line L30 (-12.9, -38.3865) -> (-9.9, -38.3865)
  line L31 (-9.9, -38.3865) -> (-9.9, -23)
  line L32 (-9.9, -23) -> (-9.9, -59.229)
  line L33 (-7.95, -37.4) -> (-24, -37.4)
  line L34 (-24, -37.4) -> (19, -37.4)
  line L35 (6.6674, -62.911) -> (11.3575, -59.1689)
  line L36 (11.3575, -59.1689) -> (33.6973, -87.1681)
  line L37 (33.6973, -87.1681) -> (-13.0492, -28.5792)
  line L38 (10.5027, -87.1681) -> (57.2492, -28.5792)
  line L39 (11.3713, -95.6997) -> (63.0846, -30.8857)
  line L40 (54.1, -23) -> (54.1, -59.229)
  line L41 (68.2, -37.4) -> (25.2, -37.4)
  line L42 (25.9379, -77.443) -> (18.2621, -77.443)
  line L43 (22.1, -72.6328) -> (12.2334, -72.6328)
  line L44 (12.2334, -72.6328) -> (34.893, -72.6328)
  line L45 (25.9379, -67.8227) -> (18.2621, -67.8227)
  line L46 (18.2621, -67.8227) -> (8.766, -75.3993)
  line L47 (25.9379, -67.8227) -> (39.3694, -78.5393)
  dimension "d66" = 4
  dimension "d67" = 4
  dimension "d68" = 4
  dimension "d69" = 4
  dimension "d70" = 3
  dimension "d71" = 6
  constraint midpoint L18 L20.start
  constraint perpendicular L18 L20
  constraint coincident L19 L21.start
  constraint perpendicular L19 L21
  constraint coincident L17 L22.start
  constraint perpendicular L17 L22
  constraint perpendicular L21 L23
  constraint perpendicular L21 L24
  constraint perpendicular L22 L25
  constraint perpendicular L22 L26
  constraint perpendicular L20 L27
  constraint parallel L27 L28
  constraint midpoint L15 L29.start
  constraint perpendicular L15 L29
  constraint coincident L16 L30.start
  constraint coincident L26 L30.start
  constraint perpendicular L29 L30
  constraint perpendicular L30 L31
  constraint perpendicular L30 L32
  constraint perpendicular L29 L33
  constraint perpendicular L31 L34
  constraint perpendicular L26 L35
  constraint perpendicular L35 L36
  constraint parallel L26 L37
  constraint symmetric L20 L25.end L39.start
  constraint symmetric L20 L26.end L39.end
  constraint symmetric L20 L31.end L40.start
  constraint symmetric L20 L32.end L40.end
  constraint symmetric L20 L33.end L41.start
  constraint symmetric L20 L34.end L41.end
  constraint symmetric L20 L36.end L38.start
  constraint symmetric L20 L37.end L38.end
  constraint coincident L39 L42.start
  constraint coincident L37 L42.start
  constraint coincident L38 L42.end
  constraint coincident L26 L42.end
  constraint coincident L37 L43.start
  constraint coincident L38 L43.start
  constraint parallel L42 L43
  constraint coincident L19 L44.end
  constraint parallel L43 L44
  constraint symmetric L42.start L43 L45.start
  constraint symmetric L42.end L43 L45.end
  constraint perpendicular L17 L46
  constraint perpendicular L19 L47
  constraint coincident L43.end L46
  measures "d66" distance of L20.start L20.end
  measures "d67" distance of L21.start L21.end
  measures "d68" distance of L22.start L22.end
  measures "d69" distance of L29.start L29.end
  measures "d70" distance of L30.start L30.end
  measures "d71" distance of L22.end L35.end
extrude "押し出し12" cut sketch "スケッチ15" against normal blind 9 contours L26 L31 L32 L33 L34 L35 L37 | L25 L26 L35 L36 L37 L46 | L24 L36 L37 L39 L44 | L36 L37 L38 L42 | L25 L26 L38 L43 L44 | L23 L24 L38 L39 L40 L41 L47 | L24 L25 L26 L27 L28 L39 L42
fillet "フィレット6" radius 2 14 edges at (-19.0257, 78.4, 0.5) (-25.1743, 78.4, 0.5) (-29.7758, 72.6328, 0.5) (-14.4242, 72.6328, 0.5) (9.9, 42.1465, 0.5) (9.9, 37.4, 0.5) (6.0113, 37.4, 0.5) (-18.2621, 67.8227, 0.5) (-13.572, 71.5647, 0.5) (-30.628, 71.5647, 0.5) (-54.1, 42.1465, 0.5) (-54.1, 37.4, 0.5) (-50.2113, 37.4, 0.5) (-25.9379, 67.8227, 0.5)